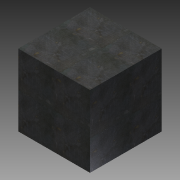
# Autodesk Inventor part: seat0
Saved by Autodesk Inventor 2015 (Build 190159000, 159)
## iProperties
Created: 2022-11-07
Part Number: seat0
Material: Generic
Document SubType Name: Modeling
Designer: Pavel Brodský
Density: 1 g/cm^3
Appearance: Default
Author: Pavel Brodský
Autodesk Inventor part; units mm, degrees
ref_plane "YZ Plane" through (0, 0, 0) normal (1, 0, 0) x (0, 1, 0)
ref_plane "XZ Plane" through (0, 0, 0) normal (0, 1, 0) x (-1, 0, 0)
ref_plane "XY Plane" through (0, 0, 0) normal (0, 0, 1) x (1, 0, 0)
sketch "Náčrt1" plane through (0, 0, 0) normal (0, 1, 0) x (-1, 0, 0)
  line L0 (0, 0) -> (-300, 0)
  line L1 (-300, 0) -> (-300, -300)
  line L2 (-300, -300) -> (0, -300)
  line L3 (0, -300) -> (0, 0)
  dimension "d0" = 300
  dimension "d1" = 300
  constraints: 8 end point, 2 parallel, 1 horizontal, 1 perpendicular
  measures "d0" distance of L2.end L0.start
  measures "d1" distance between parallel lines of L3 L1
extrude "Vysunutí1" add sketch "Náčrt1" along normal blind 300
